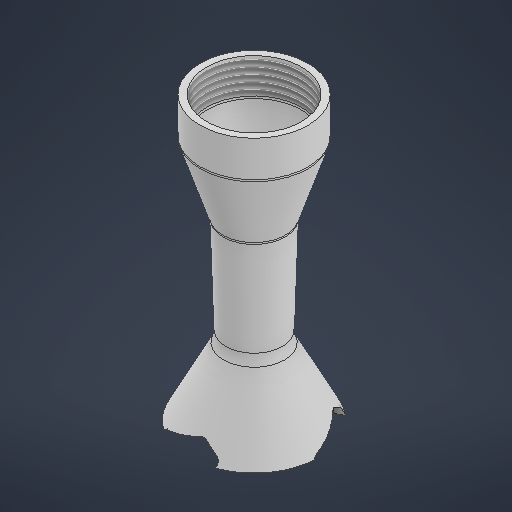
# Autodesk Inventor part: Blender_Lower Housing
Saved by Autodesk Inventor 2027.1 (Build 311270010, 270A)
## iProperties
Created: 2026-10-18
Part Number: Blender_Lower Housing
Material: Generic
Document SubType Name: Modeling
Designer: MSIPC
Density: 1 g/cm^3
Appearance: Default
Author: MSIPC
Autodesk Inventor part; units mm, degrees
ref_plane "YZ Plane" through (0, 0, 0) normal (1, 0, 0) x (0, 1, 0)
ref_plane "XZ Plane" through (0, 0, 0) normal (0, 1, 0) x (-1, 0, 0)
ref_plane "XY Plane" through (0, 0, 0) normal (0, 0, 1) x (1, 0, 0)
sketch "Sketch1" plane through (0, 0, 0) normal (0, 0, 1) x (1, 0, 0)
  line L0 (0, 0) -> (0, 127.103)
  line L1 (-26.8682, 0) -> (-11.1608, 30.7378)
  line L2 (-10.0698, 35.5812) -> (-11.4094, 81.2876)
  line L3 (-11.5547, 82.1259) -> (-21.8535, 113.8562)
  line L4 (-24.8535, 113.3816) -> (-14.5408, 81.6085)
  line L5 (-14.3955, 80.7702) -> (-13.086, 36.0931)
  line L6 (-14.1771, 31.2497) -> (-30.146, 0)
  line L7 (0, 0) -> (-30.073, 0)
  line L8 (-25, 130.9999) -> (-25, 114.3077)
  line L9 (-22, 130.9999) -> (-22, 114.7824)
  arc A0 (-22, 114.7824) -> (-21.8535, 113.8562) centre (-19, 114.7824) ccw
  arc A1 (-25, 114.3077) -> (-24.8535, 113.3816) centre (-22, 114.3077) ccw
  line L10 (-22, 130.9999) -> (-25, 130.9999)
  arc A2 (-11.4094, 81.2876) -> (-11.5547, 82.1259) centre (-14.4081, 81.1997) ccw
  arc A3 (-14.3955, 80.7702) -> (-14.5408, 81.6085) centre (-17.3942, 80.6823) ccw
  arc A4 (-11.1608, 30.7378) -> (-10.0698, 35.5812) centre (-20.0655, 35.2882) ccw
  arc A5 (-14.1771, 31.2497) -> (-13.086, 36.0931) centre (-23.0818, 35.8001) ccw
  line L11 (-30.146, 0) -> (-26.8682, 0)
  point P0 (-10.1271, 46.8182)
  point P1 (-10.1693, 35)
  point P2 (-14.4229, 81.7045)
  point P3 (-11.422, 81.7172)
  dimension "d16" = 3
  dimension "d29" = 25
  dimension "d30" = 3
  dimension "d31" = 3
  dimension "d32" = 3
  dimension "d33" = 3
  dimension "d34" = 3
  dimension "d35" = 10
  dimension "d36" = 10
  constraints: 24 end point, 12 point on circle, 12 tangent, 6 centre point, 2 horizontal, 2 point on line, 2 vertical, 1 parallel
  measures "d16" distance between parallel lines of L3 L4
  measures "d29" distance between parallel lines of L0 L8
  measures "d30" distance between parallel lines of L8 L9
  measures "d31" radius of A0
  measures "d32" radius of A1
  measures "d33" radius of A2
  measures "d34" radius of A3
  measures "d35" radius of A4
  measures "d36" radius of A5
revolve "Revolution1" add sketch "Sketch1" angle 360 about axis through (0, 0, 0) along (0, 1, 0)
sketch "Sketch4" plane through (0, 0, 0) normal (0, 0, 1) x (1, 0, 0)
  line L0 (-15.2014, 1.3174) -> (1.643, 7.3241)
  line L1 (4.3087, 6.9985) -> (9.259, 3.7155)
  line L2 (7.6009, -1.7846) -> (-17.1937, -1.7846)
  line L3 (-17.1937, -1.7846) -> (-17.1937, -1.5083)
  arc A0 (4.3087, 6.9985) -> (1.643, 7.3241) centre (2.6506, 4.4983) ccw
  arc A1 (7.6009, -1.7846) -> (9.259, 3.7155) centre (7.6009, 1.2154) ccw
  arc A2 (-15.2014, 1.3174) -> (-17.1937, -1.5083) centre (-14.1937, -1.5083) ccw
  point P0 (0, 0)
  dimension "d21" = 3
  constraints: 8 end point, 6 point on circle, 6 tangent, 3 centre point, 2 equal radius, 1 horizontal, 1 perpendicular
  measures "d21" radius of A0
extrude "Extrusion1" cut sketch "Sketch4" along normal blind 47.5
pattern_circular "Circular Pattern1" count 3 over 360 about axis through (0, -10, 0) along (0, 1, 0) of "Extrusion1"
thread "Thread1" size "M45x3" class "6H" standard "ANSI Metric M Profile" length 15
body "Solid1"
